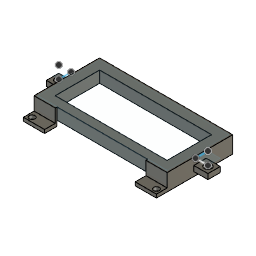
Buttons mount (Autodesk Fusion 360 design; units mm, degrees)
Autodesk Fusion 360 part; units mm, degrees
sketch "Sketch1" plane through (0, 0, 0) normal (0, 0, 1) x (1, 0, 0)
  line L0 (0, 0) -> (73, 0)
  line L1 (73, 0) -> (73, 35)
  line L2 (73, 35) -> (0, 35)
  line L3 (0, 35) -> (0, 0)
  dimension "d1" = 73
  dimension "d2" = 35
  constraint horizontal L0
  constraint vertical L1
  constraint horizontal L2
  constraint vertical L3
  constraint coincident L0.start L3.end
  measures "d1" distance of L0.start L0.end
  measures "d2" distance of L0.start L2.end
extrude "Extrude1" add sketch "Sketch1" along normal blind 7 makes body 1
sketch "Sketch2" plane through (0, 0, 7) normal (0, 0, 1) x (-1, 0, 0)
  line L0 (0, -35) -> (0, 0)
  line L1 (0, 0) -> (-73, 0)
  line L2 (-73, 0) -> (-73, -35)
  line L3 (-73, -35) -> (0, -35)
  line L4 (-68, -5) -> (-5, -5)
  line L5 (-5, -5) -> (-5, -30)
  line L6 (-5, -30) -> (-68, -30)
  line L7 (-68, -30) -> (-68, -5)
  line L8 (-68, -5) -> (-5, -30) construction
  line L9 (-5, -5) -> (-68, -30) construction
  point P0 (-36.5, -17.5)
  dimension "d5" = 63
  dimension "d6" = 25
  constraint horizontal L4
  constraint perpendicular L4 L5
  constraint parallel L4 L6
  constraint parallel L5 L7
  constraint coincident L8 P0
  constraint coincident L9 P0
  measures "d5" distance of L5.end L6.end
  measures "d6" distance of L4.end L5.end
extrude "Extrude2" cut sketch "Sketch2" against normal blind 654764 contours L4 L5 L6 L7 bodies 1
sketch "Sketch3" plane through (0, 0, 0) normal (0, 0, -1) x (1, 0, 0)
  line L0 (5, -30) -> (5, -5)
  line L1 (5, -5) -> (68, -5)
  line L2 (68, -5) -> (68, -30)
  line L3 (68, -30) -> (5, -30)
  line L4 (0, 0) -> (0, -35)
  line L5 (0, -35) -> (73, -35)
  line L6 (73, -35) -> (73, 0)
  line L7 (73, 0) -> (0, 0)
  line L8 (36.5, -35) -> (36.5, 0)
  line L9 (73, -17.5) -> (0, -17.5)
  line L10 (-1, 1) -> (74, 1)
  line L11 (74, 1) -> (74, -36)
  line L12 (74, -36) -> (-1, -36)
  line L13 (-1, -36) -> (-1, 1)
  line L14 (-1, 1) -> (74, -36) construction
  line L15 (74, 1) -> (-1, -36) construction
  point P0 (36.5, -17.5)
  constraint midpoint L5 L8.start
  constraint midpoint L7 L8.end
  constraint midpoint L6 L9.start
  constraint midpoint L4 L9.end
  constraint horizontal L10
  constraint perpendicular L10 L11
  constraint parallel L10 L12
  constraint parallel L11 L13
  constraint coincident L14 P0
  constraint coincident L15 P0
  constraint midpoint L9 P0
extrude "Extrude3" add sketch "Sketch3" along normal blind 2 separate body makes body 2
extrude "Extrude4" cut 1 faces at (47, 1.6667, 7) along direction (0, 0, -1) blind 0.5 on bodies 1 bodies 1
sketch "Sketch4" plane through (73, 0, 0) normal (1, 0, 0) x (0, 1, 0)
  line L0 (35, 6.5) -> (0, 6.5)
  line L1 (0, 6.5) -> (0, 0)
  line L2 (0, 0) -> (35, 0)
  line L3 (35, 0) -> (35, 6.5)
  line L4 (17.5, 6.5) -> (17.5, 3.5)
  line L5 (21, 3.5) -> (14, 3.5)
  line L6 (14, 3.5) -> (14, 6.5)
  line L7 (14, 6.5) -> (21, 6.5)
  line L8 (21, 6.5) -> (21, 3.5)
  line L9 (21, 3.5) -> (14, 6.5) construction
  line L10 (14, 3.5) -> (21, 6.5) construction
  point P0 (17.5, 5)
  dimension "d13" = 3
  dimension "d14" = 7
  constraint midpoint L0 L4.start
  constraint perpendicular L0 L4
  constraint horizontal L5
  constraint perpendicular L5 L6
  constraint parallel L5 L7
  constraint parallel L6 L8
  constraint coincident L9 P0
  constraint coincident L10 P0
  constraint midpoint L4 P0
  measures "d13" distance of L4.start L4.end
  measures "d14" distance of L6.end L7.end
extrude "Extrude5" add sketch "Sketch4" along normal blind 9 contours L0 L4 L5 L7 L8 | L0 L4 L5 L6 L7 bodies 1
extrude "Extrude6" add 1 faces at (82, 16.3333, 4.5) along direction (-1, 0, 0) blind 91 on bodies 1 bodies 1
sketch "Sketch5" plane through (0, 0, 6.5) normal (0, 0, 1) x (-1, 0, 0)
  line L0 (-5, -21) -> (-5, -30)
  line L1 (-5, -30) -> (-68, -30)
  line L2 (-68, -30) -> (-68, -21)
  line L3 (-68, -21) -> (-5, -21)
  line L4 (0, -14) -> (0, 0)
  line L5 (0, 0) -> (-73, 0)
  line L6 (-73, 0) -> (-73, -14)
  line L7 (-73, -14) -> (-82, -14)
  line L8 (-82, -14) -> (-82, -21)
  line L9 (-82, -21) -> (-73, -21)
  line L10 (-73, -21) -> (-73, -35)
  line L11 (-73, -35) -> (0, -35)
  line L12 (0, -35) -> (0, -21)
  line L13 (0, -21) -> (9, -21)
  line L14 (9, -21) -> (9, -14)
  line L15 (9, -14) -> (0, -14)
  line L16 (-5, -14) -> (-68, -14)
  line L17 (-68, -14) -> (-68, -5)
  line L18 (-68, -5) -> (-5, -5)
  line L19 (-5, -5) -> (-5, -14)
  line L20 (-5, -21) -> (-5, -14)
  line L21 (-68, -21) -> (-68, -14)
  constraint coincident L0.start L3.end
  constraint coincident L16.start L19.end
  constraint coincident L2.end L3.start
  constraint coincident L16.end L17.start
extrude "Extrude7" cut sketch "Sketch5" against normal blind 80 contours L3 L16 L20 L21 bodies 1
sketch "Sketch6" plane through (0, 0, 6.5) normal (0, 0, 1) x (-1, 0, 0)
  line L0 (-5, -5) -> (-5, -30)
  line L1 (-5, -30) -> (-68, -30)
  line L2 (-68, -30) -> (-68, -5)
  line L3 (-68, -5) -> (-5, -5)
  line L4 (0, -14) -> (0, 0)
  line L5 (0, 0) -> (-73, 0)
  line L6 (-73, 0) -> (-73, -14)
  line L7 (-73, -14) -> (-82, -14)
  line L8 (-82, -14) -> (-82, -21)
  line L9 (-82, -21) -> (-73, -21)
  line L10 (-73, -21) -> (-73, -35)
  line L11 (-73, -35) -> (0, -35)
  line L12 (0, -35) -> (0, -21)
  line L13 (0, -21) -> (9, -21)
  line L14 (9, -21) -> (9, -14)
  line L15 (9, -14) -> (0, -14)
  line L16 (9, -21) -> (2, -21)
  line L17 (2, -14) -> (2, -21)
  line L18 (-82, -14) -> (-75, -14)
  line L19 (-75, -21) -> (-75, -14)
  constraint coincident L13.end L14.start
  constraint coincident L13 L16.end
  constraint coincident L15 L17.start
  constraint perpendicular L13 L17
  constraint coincident L7.end L8.start
  constraint coincident L7 L18.end
  constraint coincident L9 L19.start
  constraint perpendicular L7 L19
sketch "Sketch7" plane through (0, 0, 6.5) normal (0, 0, 1) x (-1, 0, 0)
  line L0 (2, -21) -> (9, -14)
  line L1 (9, -14) -> (9, -21)
  line L2 (9, -21) -> (2, -14)
  line L3 (-75, -21) -> (-82, -14)
  line L4 (-82, -14) -> (-82, -21)
  line L5 (-82, -21) -> (-75, -14)
  circle A0 centre (-78.5, -17.5) radius 2.1
  circle A1 centre (5.5, -17.5) radius 2.1
  dimension "d21" = 4.2
  dimension "d22" = 4.2
  constraint vertical L1
  constraint perpendicular L0 L2
  constraint perpendicular L0 L3
  constraint parallel L1 L4
  constraint perpendicular L3 L5
  constraint midpoint L3 A0.centre
  constraint midpoint L2 A1.centre
  measures "d21" diameter of A0
  measures "d22" diameter of A1
extrude "Extrude8" cut sketch "Sketch7" against normal blind 38746 contours L0 L2 A1 | L0 L2 A1 | L0 L2 A1 | L0 L2 A1 | L3 L5 A0 | L3 L5 A0 | L3 L5 A0 | L3 L5 A0 bodies 1
extrude "Extrude9" add 1 faces at (36.5, -0.6667, -2) along direction (0, 0, -1) blind 1 on bodies 2 bodies 2
sketch "Sketch8" plane through (0, 36, 0) normal (0, 1, 0) x (-1, 0, 0)
  line L0 (1, 0) -> (-74, 0)
  line L1 (-74, 0) -> (-74, -3)
  line L2 (-74, -3) -> (1, -3)
  line L3 (1, -3) -> (1, 0)
  line L4 (-74, -3) -> (-69, -3)
  line L5 (-69, -3) -> (-69, -1)
  line L6 (-69, -1) -> (-74, -1)
  line L7 (-74, -1) -> (-74, -3)
  line L8 (1, -3) -> (-4, -3)
  line L9 (-4, -3) -> (-4, -1)
  line L10 (-4, -1) -> (1, -1)
  line L11 (1, -1) -> (1, -3)
  dimension "d27" = 5
  dimension "d28" = 2
  constraint horizontal L4
  constraint vertical L5
  constraint horizontal L6
  constraint vertical L7
  constraint coincident L1.end L2.start
  constraint horizontal L8
  constraint vertical L9
  constraint horizontal L10
  constraint vertical L11
  constraint coincident L2.end L3.start
  measures "d27" distance of L2.end L8.end
  measures "d28" distance of L2.end L10.end
extrude "Extrude10" add sketch "Sketch8" along normal blind 6 contours L2 L3 L8 L9 L10 L11 | L1 L2 L4 L5 L6 L7 bodies 2
sketch "Sketch9" plane through (0, 0, 0) normal (0, -1, 0) x (1, 0, 0)
  line L0 (73, 6.5) -> (0, 6.5)
  line L1 (0, 6.5) -> (0, 0)
  line L2 (0, 0) -> (73, 0)
  line L3 (73, 0) -> (73, 6.5)
sketch "Sketch10" plane through (0, -1, 0) normal (0, -1, 0) x (1, 0, 0)
  line L0 (74, 0) -> (-1, 0)
  line L1 (-1, 0) -> (-1, -3)
  line L2 (-1, -3) -> (74, -3)
  line L3 (74, -3) -> (74, 0)
  line L4 (-1, -3) -> (4, -3)
  line L5 (4, -3) -> (4, -1)
  line L6 (4, -1) -> (-1, -1)
  line L7 (-1, -1) -> (-1, -3)
  line L8 (74, -3) -> (69, -3)
  line L9 (69, -3) -> (69, -1)
  line L10 (69, -1) -> (74, -1)
  line L11 (74, -1) -> (74, -3)
  dimension "d31" = 5
  dimension "d32" = 2
  dimension "d33" = 5
  dimension "d34" = 2
  constraint horizontal L4
  constraint vertical L5
  constraint horizontal L6
  constraint vertical L7
  constraint coincident L1.end L2.start
  constraint horizontal L8
  constraint vertical L9
  constraint horizontal L10
  constraint vertical L11
  constraint coincident L2.end L3.start
  measures "d31" distance of L1.end L4.end
  measures "d32" distance of L1.end L6.end
  measures "d33" distance of L2.end L8.end
  measures "d34" distance of L2.end L10.end
extrude "Extrude11" add sketch "Sketch10" along normal blind 6 contours L2 L3 L8 L9 L10 L11 | L1 L2 L4 L5 L6 L7 bodies 2
sketch "Sketch11" plane through (0, 0, -3) normal (0, 0, -1) x (1, 0, 0)
  line L0 (0, 0) -> (73, 0)
  line L1 (73, 0) -> (73, -35)
  line L2 (73, -35) -> (0, -35)
  line L3 (0, -35) -> (0, 0)
  line L4 (4, -36) -> (69, -36)
  line L5 (69, -36) -> (69, -42)
  line L6 (69, -42) -> (74, -42)
  line L7 (74, -42) -> (74, 7)
  line L8 (74, 7) -> (69, 7)
  line L9 (69, 7) -> (69, 1)
  line L10 (69, 1) -> (4, 1)
  line L11 (4, 1) -> (4, 7)
  line L12 (4, 7) -> (-1, 7)
  line L13 (-1, 7) -> (-1, -42)
  line L14 (-1, -42) -> (4, -42)
  line L15 (4, -42) -> (4, -36)
  line L16 (-1, 7) -> (-1, 2)
  line L17 (-1, 2) -> (4, 7)
  line L18 (-1, 7) -> (4, 2)
  line L19 (69, -42) -> (69, -37)
  line L20 (69, -37) -> (74, -42)
  line L21 (74, -42) -> (74, -37)
  line L22 (69, -42) -> (74, -37)
  circle A0 centre (1.5, 4.5) radius 1.6
  circle A1 centre (71.5, -39.5) radius 1.6
  circle A2 centre (71.5, 4.5) radius 1.6
  line L23 (-1, -42) -> (-1, -37)
  line L24 (-1, -37) -> (4, -42)
  line L25 (4, -42) -> (4, -37)
  line L26 (4, -37) -> (-1, -42)
  circle A3 centre (1.5, -39.5) radius 1.6
  dimension "d37" = 5
  dimension "d38" = 5
  dimension "d39" = 3.2
  dimension "d40" = 3.2
  dimension "d41" = 3.2
  dimension "d42" = 3.2
  constraint coincident L12.end L13.start
  constraint perpendicular L12 L16
  constraint coincident L11.end L12.start
  constraint coincident L11 L18.end
  constraint perpendicular L17 L18
  constraint coincident L5.end L6.start
  constraint coincident L5 L19.end
  constraint coincident L6.end L7.start
  constraint coincident L7 L21.end
  constraint midpoint L18 A0.centre
  constraint midpoint L22 A1.centre
  constraint coincident L13.end L14.start
  constraint coincident L13 L23.end
  constraint coincident L14.end L15.start
  constraint coincident L15 L25.end
  constraint midpoint L24 A3.centre
  measures "d37" distance of L12.end L16.end
  measures "d38" distance of L5.end L19.end
  measures "d39" diameter of A0
  measures "d40" diameter of A1
  measures "d41" diameter of A2
  measures "d42" diameter of A3
extrude "Extrude12" cut sketch "Sketch11" against normal blind 40 contours L24 L26 A3 | L24 L26 A3 | L20 L22 A1 | L20 L22 A1 | L24 L26 A3 | L24 L26 A3 | L20 L22 A1 | L20 L22 A1 | L17 L18 A0 | L17 L18 A0 | L17 L18 A0 | L17 L18 A0 | A2 bodies 2
sketch "Sketch12" plane through (0, -1, 0) normal (0, -1, 0) x (1, 0, 0)
  line L0 (69, -3) -> (69, -1)
  line L1 (69, -1) -> (74, -1)
  line L2 (74, -1) -> (74, 0)
  line L3 (74, 0) -> (-1, 0)
  line L4 (-1, 0) -> (-1, -1)
  line L5 (-1, -1) -> (4, -1)
  line L6 (4, -1) -> (4, -3)
  line L7 (4, -3) -> (69, -3)
  line L8 (69, -1) -> (69, 0)
  line L9 (4, -1) -> (4, 0)
  constraint coincident L0.end L1.start
  constraint coincident L3 L8.end
  constraint perpendicular L3 L8
  constraint coincident L5.end L6.start
  constraint coincident L3 L9.end
  constraint perpendicular L3 L9
extrude "Extrude13" cut sketch "Sketch12" against normal blind 1 contours L0 L3 L6 L7 L8 L9 bodies 2
extrude "Extrude14" add 1 faces at (48.6667, 35.6667, 0) along direction (0, 0, 1) blind 6.5 on bodies 2 bodies 1 2
extrude "Extrude15" add 1 faces at (4, -2.6667, -2.3333) along direction (1, 0, 0) blind 7 on bodies 1 bodies 1
extrude "Extrude16" add 1 faces at (69, -2.6667, -2.3333) along direction (-1, 0, 0) blind 7 on bodies 1 bodies 1
extrude "Extrude17" add 2 faces at (74.8, 17.5, 3.5) (-1.8, 17.5, 3.5) along direction (0, 0, -1) blind 4 on bodies 1 bodies 1
sketch "Sketch13" plane through (0, 0, 6.5) normal (0, 0, 1) x (-1, 0, 0)
  line L0 (9, -14) -> (1, -14)
  line L1 (1, -14) -> (1, -21)
  line L2 (1, -21) -> (9, -21)
  line L3 (9, -21) -> (9, -14)
  line L4 (-82, -14) -> (-74, -14)
  line L5 (-74, -14) -> (-74, -21)
  line L6 (-74, -21) -> (-82, -21)
  line L7 (-82, -21) -> (-82, -14)
  constraint horizontal L0
  constraint vertical L1
  constraint horizontal L2
  constraint vertical L3
  constraint horizontal L4
  constraint vertical L5
  constraint horizontal L6
  constraint vertical L7
extrude "Extrude18" cut sketch "Sketch13" against normal blind 4 bodies 1
extrude "Extrude19" cut 2 faces at (2.3333, 42, -1.6667) (72.3333, 42, -1.6667) along direction (0, -1, 0) blind 6 on bodies 1 bodies 1
extrude "Extrude20" cut 1 faces at (49, 36, 0.1667) along direction (0, -1, 0) blind 0.025 on bodies 1 bodies 1
extrude "Extrude21" cut 2 faces at (70, -1, 1.5) (7, -1, 4) along direction (0, 1, 0) blind 0.025 on bodies 1 bodies 1
equation "d17 = -9 mm - 73 mm - 9 mm"
